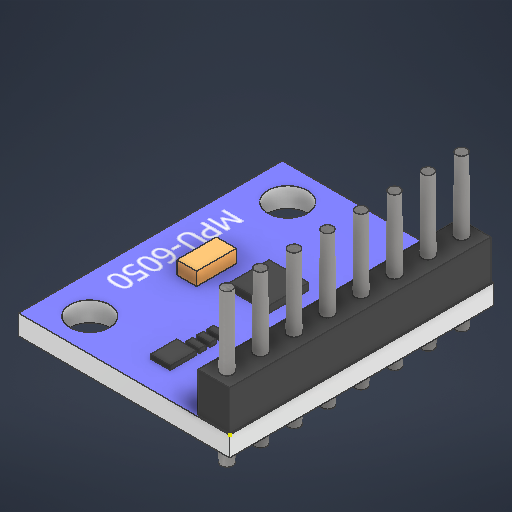
# Autodesk Inventor part: MPU-6050
Saved by Autodesk Inventor 2026.2 (Build 302298010, 298A)
## iProperties
Created: 2026-04-26
Part Number: MPU-6050
Material: ABS 플라스틱
Document SubType Name: Modeling
Designer: work
Density: 1.06 g/cm^3
Appearance: 매끄러움 - 흰색
Author: work
Autodesk Inventor part; units mm, degrees
ref_plane "YZ Plane" through (0, 0, 0) normal (1, 0, 0) x (0, 1, 0)
ref_plane "XZ Plane" through (0, 0, 0) normal (0, 1, 0) x (-1, 0, 0)
ref_plane "XY Plane" through (0, 0, 0) normal (0, 0, 1) x (1, 0, 0)
sketch "스케치1" plane through (0, 0, 0) normal (0, 1, 0) x (-1, 0, 0)
  line L0 (0, 0) -> (16, 0)
  line L1 (16, 0) -> (16, -20)
  line L2 (16, -20) -> (0, -20)
  line L3 (0, -20) -> (0, 0)
  circle A0 centre (13.1, -2.5) radius 1.5
  circle A1 centre (13.1, -17.5) radius 1.5
  line L4 (13.1, -2.5) -> (13.1, -17.5) construction
  line L5 (16, -10) -> (0, -10) construction
  point P0 (13.1, -10)
  dimension "d0" = 16
  dimension "d1" = 20
  dimension "d2" = 3
  dimension "d3" = 3
  dimension "d4" = 15
  dimension "d5" = 2.9
  constraints: 12 end point, 3 midpoint, 2 centre point, 2 parallel, 1 horizontal, 1 perpendicular, 1 point on line, 1 vertical
  measures "d0" distance of L1.end L2.end
  measures "d1" distance of L0.end L1.end
  measures "d2" diameter of A0
  measures "d3" diameter of A1
  measures "d4" distance of L4.start L4.end
  measures "d5" distance between parallel lines of L1 L4
extrude "돌출1" add sketch "스케치1" along normal blind 1.5
sketch "스케치2" plane through (0, 1.5, 0) normal (0, 1, 0) x (1, 0, 0)
  line L0 (-2.5, 0.1) -> (-0.1, 0.1)
  line L1 (-0.1, 0.1) -> (-0.1, 19.9)
  line L2 (-0.1, 19.9) -> (-2.5, 19.9)
  line L3 (-2.5, 19.9) -> (-2.5, 0.1)
  line L4 (0, 0) -> (0, 20) projected
  line L5 (0, 10) -> (-16, 10) construction
  line L6 (-16, 20) -> (-16, 0) projected
  line L7 (0, 20) -> (-16, 20) projected
  line L8 (-12.5, 8.5) -> (-11, 8.5)
  line L9 (-11, 8.5) -> (-11, 11.5)
  line L10 (-11, 11.5) -> (-12.5, 11.5)
  line L11 (-12.5, 11.5) -> (-12.5, 8.5)
  line L12 (-9.5, 9.5) -> (-6.5, 9.5)
  line L13 (-6.5, 9.5) -> (-6.5, 12.5)
  line L14 (-6.5, 12.5) -> (-9.5, 12.5)
  line L15 (-9.5, 12.5) -> (-9.5, 9.5)
  line L16 (-8, 9.5) -> (-8, 12.5) construction
  line L17 (-8, 2) -> (-6.5, 2)
  line L18 (-6.5, 2) -> (-6.5, 4)
  line L19 (-6.5, 4) -> (-8, 4)
  line L20 (-8, 4) -> (-8, 2)
  line L21 (-16, 0) -> (0, 0) projected
  line L22 (-7.5, 4.2) -> (-6.5, 4.2)
  line L23 (-6.5, 4.2) -> (-6.5, 4.7)
  line L24 (-6.5, 4.7) -> (-7.5, 4.7)
  line L25 (-7.5, 4.7) -> (-7.5, 4.2)
  line L26 (-7.5, 5) -> (-6.5, 5)
  line L27 (-6.5, 5) -> (-6.5, 5.5)
  line L28 (-6.5, 5.5) -> (-7.5, 5.5)
  line L29 (-7.5, 5.5) -> (-7.5, 5)
  line L30 (-7.5, 5.8) -> (-6.5, 5.8)
  line L31 (-6.5, 5.8) -> (-6.5, 6.3)
  line L32 (-6.5, 6.3) -> (-7.5, 6.3)
  line L33 (-7.5, 6.3) -> (-7.5, 5.8)
  point P0 (-0.1, 10)
  point P1 (-12.5, 10)
  point P2 (-8, 10)
  point P3 (-7.25, 2)
  point P4 (-6.5, 3)
  point P5 (-7.25, 4)
  point P6 (-7, 5.5)
  dimension "d8" = 2.4
  dimension "d9" = 0.1
  dimension "d10" = 0.1
  dimension "d11" = 1.5
  dimension "d12" = 3
  dimension "d13" = 3.5
  dimension "d14" = 3
  dimension "d15" = 3
  dimension "d16" = 0.5
  dimension "d17" = 2
  dimension "d18" = 1.5
  dimension "d19" = 2
  dimension "d20" = 4
  dimension "d21" = 0.5
  dimension "d22" = 1
  dimension "d23" = 0.2
  dimension "d24" = 4
  dimension "d25" = 0.5
  dimension "d26" = 1
  dimension "d27" = 0.3
  dimension "d28" = 0.5
  dimension "d29" = 1
  dimension "d30" = 0.3
  constraints: 60 end point, 14 parallel, 11 midpoint, 7 horizontal, 7 perpendicular, 3 point on line, 2 collinear
  measures "d8" distance of L1.end L2.end
  measures "d9" distance between parallel lines of L7 L2
  measures "d10" distance between parallel lines of L4 L1
  measures "d11" distance of L9.end L10.end
  measures "d12" distance of L10.end L8.start
  measures "d13" distance between parallel lines of L6 L11
  measures "d14" distance of L14.end L13.end
  measures "d15" distance of L13.end L12.end
  measures "d16" distance of L16.start point (-8, 10)
  measures "d17" distance of L19.end L17.start
  measures "d18" distance of L18.end L19.end
  measures "d19" distance from line of L21 point (-7.25, 2)
  measures "d20" distance from line of L3 point (-6.5, 3)
  measures "d21" distance of L22.end L23.end
  measures "d22" distance of L23.end L24.end
  measures "d23" vertical distance of point (-7.25, 4) L22.end
  measures "d24" distance from line of L3 L23.end
  measures "d25" distance of L26.end L27.end
  measures "d26" distance of L27.end L29.start
  measures "d27" distance between parallel lines of L24 L26
  measures "d28" distance of L30.end L31.end
  measures "d29" distance of L31.end L33.start
  measures "d30" distance from line of point (-7, 5.5) L30
extrude "돌출2" add sketch "스케치2" along normal blind 0.5 contours L15 L14 L13 L12
extrude "돌출3" add sketch "스케치2" along normal blind 1 contours L11 L10 L9 L8
extrude "돌출4" add sketch "스케치2" along normal blind 0.3 contours L20 L19 L18 L17 | L25 L24 L23 L22 | L29 L28 L27 L26 | L33 L32 L31 L30
extrude "돌출5" add sketch "스케치2" along normal blind 3 contours L3 L2 L1 L0
sketch "스케치3" plane through (0, 1.5, 0) normal (0, 1, 0) x (1, 0, 0)
  line L0 (-13.4839, 14.7302) -> (-13.4839, 5.3983) construction
  line L1 (-13.4839, 5.3983) -> (-15.0459, 5.3983) construction
  line L2 (-15.0459, 5.3983) -> (-15.0459, 14.7302) construction
  line L3 (-15.0459, 14.7302) -> (-13.4839, 14.7302) construction
  point P0 (0, 0)
  dimension "d0" = 16
  dimension "d1" = 20
  dimension "d2" = 3
  dimension "d3" = 3
  dimension "d4" = 15
  dimension "d5" = 2.9
  constraints: 2 other
sketch "스케치4" plane through (0, 0, 0) normal (0, -1, 0) x (1, 0, 0)
  line L0 (-0.1, -0.1) -> (-0.1, -19.9) projected
  line L1 (-0.1, -19.9) -> (-2.5, -19.9) projected
  line L2 (-2.5, -19.9) -> (-2.5, -0.1) projected
  line L3 (-2.5, -0.1) -> (-0.1, -0.1) projected
  line L4 (-1.3, -0.1) -> (-1.3, -19.9) construction
  circle A0 centre (-1.3, -1.1) radius 0.5
  circle A1 centre (-1.3, -3.64) radius 0.5
  circle A2 centre (-1.3, -6.18) radius 0.5
  circle A3 centre (-1.3, -8.72) radius 0.5
  circle A4 centre (-1.3, -11.26) radius 0.5
  circle A5 centre (-1.3, -13.8) radius 0.5
  circle A6 centre (-1.3, -16.34) radius 0.5
  circle A7 centre (-1.3, -18.88) radius 0.5
  point P0 (0, 0)
  dimension "d39" = 1
  dimension "d40" = 1
  dimension "d43" = 2.54
  constraints: 8 centre point, 2 end point, 2 midpoint, 1 point on line, 1 vertical, 14 other
  measures "d39" diameter of A0
  measures "d40" distance of L4.start A0.centre
  measures "d43" distance of A0.centre A1.centre
extrude "돌출6" add sketch "스케치4" along normal blind 1.5 draft -2 contours A0 | A1 | A2 | A3 | A4 | A5 | A6 | A7
extrude "돌출7" add sketch "스케치4" against normal blind 10 draft -0.5 contours A0 | A1 | A2 | A3 | A4 | A5 | A6 | A7
